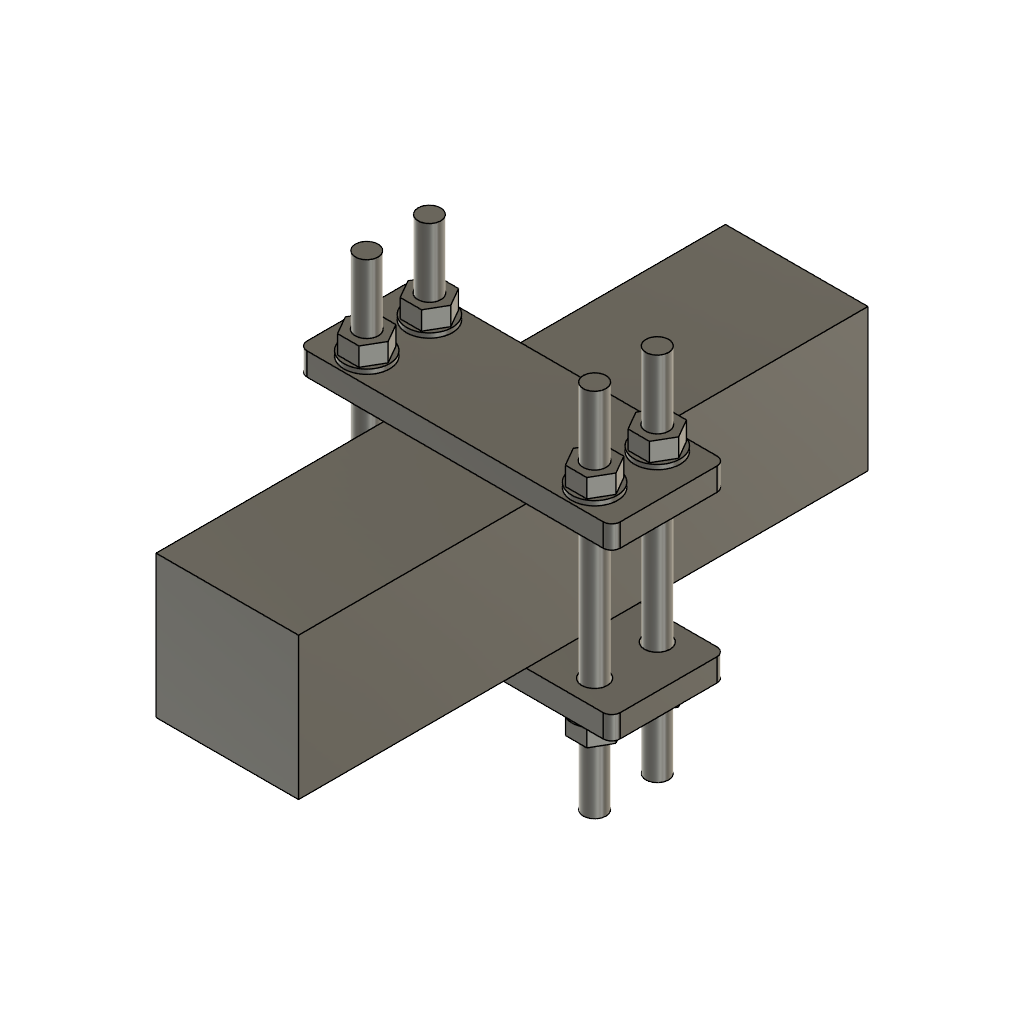
VISION_SWINE_Beam_Clamp_V1 (Autodesk Fusion 360 design; units mm, degrees)
part number: 2026-11-26-00-04-15-163
part number: 2026-11-26-00-04-15-727
part number: 2026-11-26-00-04-15-969
part number: 2026-11-26-00-04-18-167
part number: 2026-11-26-00-04-22-243
part number: 2026-11-26-00-04-23-402
part number: 2026-11-26-00-04-25-532
part number: 2026-11-26-00-04-30-687
part number: 2026-11-26-00-04-34-257
part number: 2026-11-26-00-04-42-118
part number: 2026-11-26-00-04-44-728
part number: 2026-11-26-00-04-49-048
part number: 2026-11-26-00-04-58-557
part number: 2026-11-26-00-05-03-923
part number: 2026-11-26-00-05-15-362
part number: 2026-11-26-00-05-19-142
part number: 2026-11-26-00-05-25-703
part number: 2026-11-26-00-05-39-825
part number: 2026-11-26-00-05-47-520
part number: 2026-11-26-00-06-03-111
part number: 2026-11-26-00-06-08-326
part number: 2026-11-26-00-06-16-988
part number: 2026-11-26-00-06-35-002
part number: 2026-11-26-00-06-44-910
Autodesk Fusion 360 part; units mm, degrees
ref_plane "WorkPlane1" through (-25, 0, 0) normal (1, 0, 0) x (0, 1, 0) in component "Beam_reference"
ref_plane "WorkPlane2" through (0, -100, 0) normal (0, 1, 0) x (0, 0, 1) in component "Beam_reference"
ref_plane "WorkPlane3" through (25, 0, 0) normal (1, 0, 0) x (0, 1, 0) in component "Beam_reference"
ref_plane "WorkPlane4" through (0, 100, 0) normal (0, 1, 0) x (0, 0, 1) in component "Beam_reference"
sketch "Sketch1" plane through (0, 0, 0) normal (0, 0, 1) x (1, 0, 0) in component "Beam_reference"
  line L0 (-25, -100) -> (24.9879, -99.9365)
  line L1 (24.9879, -99.9365) -> (25, 100)
  line L2 (25, 100) -> (-24.9879, 99.9365)
  line L3 (-24.9879, 99.9365) -> (-25, -100)
extrude "Rectangular blank" add sketch "Sketch1" along normal blind 50 makes body 1 in component "Beam_reference"
ref_plane "WorkPlane1" through (0, 0, -8) normal (0, 0, 1) x (1, 0, 0) in component "Lower_plate"
ref_plane "WorkPlane2" through (-55, 0, 0) normal (1, 0, 0) x (0, 1, 0) in component "Lower_plate"
ref_plane "WorkPlane3" through (0, -20, 0) normal (0, 1, 0) x (0, 0, 1) in component "Lower_plate"
ref_plane "WorkPlane4" through (55, 0, 0) normal (1, 0, 0) x (0, 1, 0) in component "Lower_plate"
ref_plane "WorkPlane5" through (0, 20, 0) normal (0, 1, 0) x (0, 0, 1) in component "Lower_plate"
sketch "Sketch1 (2)" plane through (0, 0, -8) normal (0, 0, 1) x (1, 0, 0) in component "Lower_plate"
  line L0 (-55, -20) -> (55, -20)
  line L1 (55, -20) -> (55, 20)
  line L2 (55, 20) -> (-55, 20)
  line L3 (-55, 20) -> (-55, -20)
extrude "Rectangular blank'" add sketch "Sketch1 (2)" along normal blind 8 separate body makes body 2 in component "Lower_plate"
fillet "Plate corners R" radius 3 4 edges at (-55, 20, -4) (55, 20, -4) (55, -20, -4) (-55, -20, -4) on bodies 2 in component "Lower_plate"
ref_plane "WorkPlane6" through (-40, 0, 0) normal (1, 0, 0) x (0, 1, 0) in component "Lower_plate"
ref_plane "WorkPlane7" through (0, -11, 0) normal (0, 1, 0) x (0, 0, 1) in component "Lower_plate"
sketch "Sketch2" plane through (0, 0, -8) normal (0, 0, 1) x (1, 0, 0) in component "Lower_plate"
  circle A0 centre (-40, -11) radius 4.5
  dimension "d51" = 9
  measures "d51" diameter of A0
extrude "M8 clearance 1" cut sketch "Sketch2" along normal blind 8 bodies 2 in component "Lower_plate"
ref_plane "WorkPlane8" through (0, 11, 0) normal (0, 1, 0) x (0, 0, 1) in component "Lower_plate"
sketch "Sketch3" plane through (0, 0, -8) normal (0, 0, 1) x (1, 0, 0) in component "Lower_plate"
  circle A0 centre (-40, 11) radius 4.5
  dimension "d56" = 9
  measures "d56" diameter of A0
extrude "M8 clearance 2" cut sketch "Sketch3" along normal blind 8 bodies 2 in component "Lower_plate"
ref_plane "WorkPlane9" through (40, 0, 0) normal (1, 0, 0) x (0, 1, 0) in component "Lower_plate"
sketch "Sketch4" plane through (0, 0, -8) normal (0, 0, 1) x (1, 0, 0) in component "Lower_plate"
  circle A0 centre (40, -11) radius 4.5
  dimension "d61" = 9
  measures "d61" diameter of A0
extrude "M8 clearance 3" cut sketch "Sketch4" along normal blind 8 bodies 2 in component "Lower_plate"
sketch "Sketch5" plane through (0, 0, -8) normal (0, 0, 1) x (1, 0, 0) in component "Lower_plate"
  circle A0 centre (40, 11) radius 4.5
  dimension "d64" = 9
  measures "d64" diameter of A0
extrude "M8 clearance 4" cut sketch "Sketch5" along normal blind 8 bodies 2 in component "Lower_plate"
ref_plane "WorkPlane1" through (0, 0, 50) normal (0, 0, 1) x (1, 0, 0) in component "Upper_plate"
ref_plane "WorkPlane2" through (-55, 0, 0) normal (1, 0, 0) x (0, 1, 0) in component "Upper_plate"
ref_plane "WorkPlane3" through (0, -20, 0) normal (0, 1, 0) x (0, 0, 1) in component "Upper_plate"
ref_plane "WorkPlane4" through (55, 0, 0) normal (1, 0, 0) x (0, 1, 0) in component "Upper_plate"
ref_plane "WorkPlane5" through (0, 20, 0) normal (0, 1, 0) x (0, 0, 1) in component "Upper_plate"
sketch "Sketch1 (3)" plane through (0, 0, 50) normal (0, 0, 1) x (1, 0, 0) in component "Upper_plate"
  line L0 (-55, -20) -> (55, -20)
  line L1 (55, -20) -> (55, 20)
  line L2 (55, 20) -> (-55, 20)
  line L3 (-55, 20) -> (-55, -20)
extrude "Rectangular blank''" add sketch "Sketch1 (3)" along normal blind 8 separate body makes body 3 in component "Upper_plate"
fillet "Plate corners R'" radius 3 4 edges at (-55, 20, 54) (55, 20, 54) (55, -20, 54) (-55, -20, 54) on bodies 3 in component "Upper_plate"
ref_plane "WorkPlane6" through (-40, 0, 0) normal (1, 0, 0) x (0, 1, 0) in component "Upper_plate"
ref_plane "WorkPlane7" through (0, -11, 0) normal (0, 1, 0) x (0, 0, 1) in component "Upper_plate"
sketch "Sketch2 (2)" plane through (0, 0, 50) normal (0, 0, 1) x (1, 0, 0) in component "Upper_plate"
  circle A0 centre (-40, -11) radius 4.5
  dimension "d85" = 9
  measures "d85" diameter of A0
extrude "M8 clearance 1'" cut sketch "Sketch2 (2)" along normal blind 8 bodies 3 in component "Upper_plate"
ref_plane "WorkPlane8" through (0, 11, 0) normal (0, 1, 0) x (0, 0, 1) in component "Upper_plate"
sketch "Sketch3 (2)" plane through (0, 0, 50) normal (0, 0, 1) x (1, 0, 0) in component "Upper_plate"
  circle A0 centre (-40, 11) radius 4.5
  dimension "d90" = 9
  measures "d90" diameter of A0
extrude "M8 clearance 2'" cut sketch "Sketch3 (2)" along normal blind 8 bodies 3 in component "Upper_plate"
ref_plane "WorkPlane9" through (40, 0, 0) normal (1, 0, 0) x (0, 1, 0) in component "Upper_plate"
sketch "Sketch4 (2)" plane through (0, 0, 50) normal (0, 0, 1) x (1, 0, 0) in component "Upper_plate"
  circle A0 centre (40, -11) radius 4.5
  dimension "d95" = 9
  measures "d95" diameter of A0
extrude "M8 clearance 3'" cut sketch "Sketch4 (2)" along normal blind 8 bodies 3 in component "Upper_plate"
sketch "Sketch5 (2)" plane through (0, 0, 50) normal (0, 0, 1) x (1, 0, 0) in component "Upper_plate"
  circle A0 centre (40, 11) radius 4.5
  dimension "d98" = 9
  measures "d98" diameter of A0
extrude "M8 clearance 4'" cut sketch "Sketch5 (2)" along normal blind 8 bodies 3 in component "Upper_plate"
ref_plane "WorkPlane1" through (0, 0, -40) normal (0, 0, 1) x (1, 0, 0) in component "Rod_1_ref"
ref_plane "WorkPlane2" through (-40, 0, 0) normal (1, 0, 0) x (0, 1, 0) in component "Rod_1_ref"
ref_plane "WorkPlane3" through (0, -11, 0) normal (0, 1, 0) x (0, 0, 1) in component "Rod_1_ref"
sketch "Sketch1 (4)" plane through (0, 0, -40) normal (0, 0, 1) x (1, 0, 0) in component "Rod_1_ref"
  circle A0 centre (-40, -11) radius 4
  dimension "d107" = 8
  measures "d107" diameter of A0
extrude "Smooth M8 rod envelope" add sketch "Sketch1 (4)" along normal blind 130 separate body makes body 4 in component "Rod_1_ref"
ref_plane "WorkPlane1" through (0, 0, -9.6) normal (0, 0, 1) x (1, 0, 0) in component "Washer_lower_1_ref"
ref_plane "WorkPlane2" through (-40, 0, 0) normal (1, 0, 0) x (0, 1, 0) in component "Washer_lower_1_ref"
ref_plane "WorkPlane3" through (0, -11, 0) normal (0, 1, 0) x (0, 0, 1) in component "Washer_lower_1_ref"
sketch "Sketch1 (5)" plane through (0, 0, -9.6) normal (0, 0, 1) x (1, 0, 0) in component "Washer_lower_1_ref"
  circle A0 centre (-40, -11) radius 8
  dimension "d116" = 16
  measures "d116" diameter of A0
extrude "Washer blank" add sketch "Sketch1 (5)" along normal blind 1.6 separate body makes body 5 in component "Washer_lower_1_ref"
sketch "Sketch2 (3)" plane through (0, 0, -9.6) normal (0, 0, 1) x (1, 0, 0) in component "Washer_lower_1_ref"
  circle A0 centre (-40, -11) radius 4.2
  dimension "d119" = 8.4
  measures "d119" diameter of A0
extrude "Washer bore" cut sketch "Sketch2 (3)" along normal blind 1.6 bodies 5 in component "Washer_lower_1_ref"
ref_plane "WorkPlane1" through (0, 0, -16.1) normal (0, 0, 1) x (1, 0, 0) in component "Nut_lower_1_ref"
ref_plane "WorkPlane2" through (-32.4944, 0, 0) normal (1, 0, 0) x (0, 1, 0) in component "Nut_lower_1_ref"
ref_plane "WorkPlane3" through (0, -11, 0) normal (0, 1, 0) x (0, 0, 1) in component "Nut_lower_1_ref"
ref_plane "WorkPlane4" through (-36.2472, 0, 0) normal (1, 0, 0) x (0, 1, 0) in component "Nut_lower_1_ref"
ref_plane "WorkPlane5" through (0, -4.5, 0) normal (0, 1, 0) x (0, 0, 1) in component "Nut_lower_1_ref"
ref_plane "WorkPlane6" through (-43.7528, 0, 0) normal (1, 0, 0) x (0, 1, 0) in component "Nut_lower_1_ref"
ref_plane "WorkPlane7" through (-47.5056, 0, 0) normal (1, 0, 0) x (0, 1, 0) in component "Nut_lower_1_ref"
ref_plane "WorkPlane8" through (0, -17.5, 0) normal (0, 1, 0) x (0, 0, 1) in component "Nut_lower_1_ref"
sketch "Sketch1 (6)" plane through (0, 0, -16.1) normal (0, 0, 1) x (1, 0, 0) in component "Nut_lower_1_ref"
  line L0 (-32.4944, -11) -> (-36.2472, -4.5)
  line L1 (-36.2472, -4.5) -> (-43.7528, -4.5)
  line L2 (-43.7528, -4.5) -> (-47.5056, -11)
  line L3 (-47.5056, -11) -> (-43.7528, -17.5)
  line L4 (-43.7528, -17.5) -> (-36.2472, -17.5)
  line L5 (-36.2472, -17.5) -> (-32.4944, -11)
extrude "Hex nut reference" add sketch "Sketch1 (6)" along normal blind 6.5 separate body makes body 6 in component "Nut_lower_1_ref"
ref_plane "WorkPlane9" through (-40, 0, 0) normal (1, 0, 0) x (0, 1, 0) in component "Nut_lower_1_ref"
ref_plane "WorkPlane10" through (0, -11, 0) normal (0, 1, 0) x (0, 0, 1) in component "Nut_lower_1_ref"
sketch "Sketch2 (4)" plane through (0, 0, -16.1) normal (0, 0, 1) x (1, 0, 0) in component "Nut_lower_1_ref"
  circle A0 centre (-40, -11) radius 4.05
  dimension "d144" = 8.1
  measures "d144" diameter of A0
extrude "Thread envelope bore" cut sketch "Sketch2 (4)" along normal blind 6.5 bodies 6 in component "Nut_lower_1_ref"
ref_plane "WorkPlane1" through (0, 0, 58) normal (0, 0, 1) x (1, 0, 0) in component "Washer_upper_1_ref"
ref_plane "WorkPlane2" through (-40, 0, 0) normal (1, 0, 0) x (0, 1, 0) in component "Washer_upper_1_ref"
ref_plane "WorkPlane3" through (0, -11, 0) normal (0, 1, 0) x (0, 0, 1) in component "Washer_upper_1_ref"
sketch "Sketch1 (7)" plane through (0, 0, 58) normal (0, 0, 1) x (1, 0, 0) in component "Washer_upper_1_ref"
  circle A0 centre (-40, -11) radius 8
  dimension "d153" = 16
  measures "d153" diameter of A0
extrude "Washer blank'" add sketch "Sketch1 (7)" along normal blind 1.6 separate body makes body 7 in component "Washer_upper_1_ref"
sketch "Sketch2 (5)" plane through (0, 0, 58) normal (0, 0, 1) x (1, 0, 0) in component "Washer_upper_1_ref"
  circle A0 centre (-40, -11) radius 4.2
  dimension "d156" = 8.4
  measures "d156" diameter of A0
extrude "Washer bore'" cut sketch "Sketch2 (5)" along normal blind 1.6 bodies 7 in component "Washer_upper_1_ref"
ref_plane "WorkPlane1" through (0, 0, 59.6) normal (0, 0, 1) x (1, 0, 0) in component "Nut_upper_1_ref"
ref_plane "WorkPlane2" through (-32.4944, 0, 0) normal (1, 0, 0) x (0, 1, 0) in component "Nut_upper_1_ref"
ref_plane "WorkPlane3" through (0, -11, 0) normal (0, 1, 0) x (0, 0, 1) in component "Nut_upper_1_ref"
ref_plane "WorkPlane4" through (-36.2472, 0, 0) normal (1, 0, 0) x (0, 1, 0) in component "Nut_upper_1_ref"
ref_plane "WorkPlane5" through (0, -4.5, 0) normal (0, 1, 0) x (0, 0, 1) in component "Nut_upper_1_ref"
ref_plane "WorkPlane6" through (-43.7528, 0, 0) normal (1, 0, 0) x (0, 1, 0) in component "Nut_upper_1_ref"
ref_plane "WorkPlane7" through (-47.5056, 0, 0) normal (1, 0, 0) x (0, 1, 0) in component "Nut_upper_1_ref"
ref_plane "WorkPlane8" through (0, -17.5, 0) normal (0, 1, 0) x (0, 0, 1) in component "Nut_upper_1_ref"
sketch "Sketch1 (8)" plane through (0, 0, 59.6) normal (0, 0, 1) x (1, 0, 0) in component "Nut_upper_1_ref"
  line L0 (-32.4944, -11) -> (-36.2472, -4.5)
  line L1 (-36.2472, -4.5) -> (-43.7528, -4.5)
  line L2 (-43.7528, -4.5) -> (-47.5056, -11)
  line L3 (-47.5056, -11) -> (-43.7528, -17.5)
  line L4 (-43.7528, -17.5) -> (-36.2472, -17.5)
  line L5 (-36.2472, -17.5) -> (-32.4944, -11)
extrude "Hex nut reference'" add sketch "Sketch1 (8)" along normal blind 6.5 separate body makes body 8 in component "Nut_upper_1_ref"
ref_plane "WorkPlane9" through (-40, 0, 0) normal (1, 0, 0) x (0, 1, 0) in component "Nut_upper_1_ref"
ref_plane "WorkPlane10" through (0, -11, 0) normal (0, 1, 0) x (0, 0, 1) in component "Nut_upper_1_ref"
sketch "Sketch2 (6)" plane through (0, 0, 59.6) normal (0, 0, 1) x (1, 0, 0) in component "Nut_upper_1_ref"
  circle A0 centre (-40, -11) radius 4.05
  dimension "d181" = 8.1
  measures "d181" diameter of A0
extrude "Thread envelope bore'" cut sketch "Sketch2 (6)" along normal blind 6.5 bodies 8 in component "Nut_upper_1_ref"
ref_plane "WorkPlane1" through (0, 0, -40) normal (0, 0, 1) x (1, 0, 0) in component "Rod_2_ref"
ref_plane "WorkPlane2" through (-40, 0, 0) normal (1, 0, 0) x (0, 1, 0) in component "Rod_2_ref"
ref_plane "WorkPlane3" through (0, 11, 0) normal (0, 1, 0) x (0, 0, 1) in component "Rod_2_ref"
sketch "Sketch1 (9)" plane through (0, 0, -40) normal (0, 0, 1) x (1, 0, 0) in component "Rod_2_ref"
  circle A0 centre (-40, 11) radius 4
  dimension "d190" = 8
  measures "d190" diameter of A0
extrude "Smooth M8 rod envelope'" add sketch "Sketch1 (9)" along normal blind 130 separate body makes body 9 in component "Rod_2_ref"
ref_plane "WorkPlane1" through (0, 0, -9.6) normal (0, 0, 1) x (1, 0, 0) in component "Washer_lower_2_ref"
ref_plane "WorkPlane2" through (-40, 0, 0) normal (1, 0, 0) x (0, 1, 0) in component "Washer_lower_2_ref"
ref_plane "WorkPlane3" through (0, 11, 0) normal (0, 1, 0) x (0, 0, 1) in component "Washer_lower_2_ref"
sketch "Sketch1 (10)" plane through (0, 0, -9.6) normal (0, 0, 1) x (1, 0, 0) in component "Washer_lower_2_ref"
  circle A0 centre (-40, 11) radius 8
  dimension "d199" = 16
  measures "d199" diameter of A0
extrude "Washer blank''" add sketch "Sketch1 (10)" along normal blind 1.6 separate body makes body 10 in component "Washer_lower_2_ref"
sketch "Sketch2 (7)" plane through (0, 0, -9.6) normal (0, 0, 1) x (1, 0, 0) in component "Washer_lower_2_ref"
  circle A0 centre (-40, 11) radius 4.2
  dimension "d202" = 8.4
  measures "d202" diameter of A0
extrude "Washer bore''" cut sketch "Sketch2 (7)" along normal blind 1.6 bodies 10 in component "Washer_lower_2_ref"
ref_plane "WorkPlane1" through (0, 0, -16.1) normal (0, 0, 1) x (1, 0, 0) in component "Nut_lower_2_ref"
ref_plane "WorkPlane2" through (-32.4944, 0, 0) normal (1, 0, 0) x (0, 1, 0) in component "Nut_lower_2_ref"
ref_plane "WorkPlane3" through (0, 11, 0) normal (0, 1, 0) x (0, 0, 1) in component "Nut_lower_2_ref"
ref_plane "WorkPlane4" through (-36.2472, 0, 0) normal (1, 0, 0) x (0, 1, 0) in component "Nut_lower_2_ref"
ref_plane "WorkPlane5" through (0, 17.5, 0) normal (0, 1, 0) x (0, 0, 1) in component "Nut_lower_2_ref"
ref_plane "WorkPlane6" through (-43.7528, 0, 0) normal (1, 0, 0) x (0, 1, 0) in component "Nut_lower_2_ref"
ref_plane "WorkPlane7" through (-47.5056, 0, 0) normal (1, 0, 0) x (0, 1, 0) in component "Nut_lower_2_ref"
ref_plane "WorkPlane8" through (0, 4.5, 0) normal (0, 1, 0) x (0, 0, 1) in component "Nut_lower_2_ref"
sketch "Sketch1 (11)" plane through (0, 0, -16.1) normal (0, 0, 1) x (1, 0, 0) in component "Nut_lower_2_ref"
  line L0 (-32.4944, 11) -> (-36.2472, 17.5)
  line L1 (-36.2472, 17.5) -> (-43.7528, 17.5)
  line L2 (-43.7528, 17.5) -> (-47.5056, 11)
  line L3 (-47.5056, 11) -> (-43.7528, 4.5)
  line L4 (-43.7528, 4.5) -> (-36.2472, 4.5)
  line L5 (-36.2472, 4.5) -> (-32.4944, 11)
extrude "Hex nut reference''" add sketch "Sketch1 (11)" along normal blind 6.5 separate body makes body 11 in component "Nut_lower_2_ref"
ref_plane "WorkPlane9" through (-40, 0, 0) normal (1, 0, 0) x (0, 1, 0) in component "Nut_lower_2_ref"
ref_plane "WorkPlane10" through (0, 11, 0) normal (0, 1, 0) x (0, 0, 1) in component "Nut_lower_2_ref"
sketch "Sketch2 (8)" plane through (0, 0, -16.1) normal (0, 0, 1) x (1, 0, 0) in component "Nut_lower_2_ref"
  circle A0 centre (-40, 11) radius 4.05
  dimension "d227" = 8.1
  measures "d227" diameter of A0
extrude "Thread envelope bore''" cut sketch "Sketch2 (8)" along normal blind 6.5 bodies 11 in component "Nut_lower_2_ref"
ref_plane "WorkPlane1" through (0, 0, 58) normal (0, 0, 1) x (1, 0, 0) in component "Washer_upper_2_ref"
ref_plane "WorkPlane2" through (-40, 0, 0) normal (1, 0, 0) x (0, 1, 0) in component "Washer_upper_2_ref"
ref_plane "WorkPlane3" through (0, 11, 0) normal (0, 1, 0) x (0, 0, 1) in component "Washer_upper_2_ref"
sketch "Sketch1 (12)" plane through (0, 0, 58) normal (0, 0, 1) x (1, 0, 0) in component "Washer_upper_2_ref"
  circle A0 centre (-40, 11) radius 8
  dimension "d236" = 16
  measures "d236" diameter of A0
extrude "Washer blank'''" add sketch "Sketch1 (12)" along normal blind 1.6 separate body makes body 12 in component "Washer_upper_2_ref"
sketch "Sketch2 (9)" plane through (0, 0, 58) normal (0, 0, 1) x (1, 0, 0) in component "Washer_upper_2_ref"
  circle A0 centre (-40, 11) radius 4.2
  dimension "d239" = 8.4
  measures "d239" diameter of A0
extrude "Washer bore'''" cut sketch "Sketch2 (9)" along normal blind 1.6 bodies 12 in component "Washer_upper_2_ref"
ref_plane "WorkPlane1" through (0, 0, 59.6) normal (0, 0, 1) x (1, 0, 0) in component "Nut_upper_2_ref"
ref_plane "WorkPlane2" through (-32.4944, 0, 0) normal (1, 0, 0) x (0, 1, 0) in component "Nut_upper_2_ref"
ref_plane "WorkPlane3" through (0, 11, 0) normal (0, 1, 0) x (0, 0, 1) in component "Nut_upper_2_ref"
ref_plane "WorkPlane4" through (-36.2472, 0, 0) normal (1, 0, 0) x (0, 1, 0) in component "Nut_upper_2_ref"
ref_plane "WorkPlane5" through (0, 17.5, 0) normal (0, 1, 0) x (0, 0, 1) in component "Nut_upper_2_ref"
ref_plane "WorkPlane6" through (-43.7528, 0, 0) normal (1, 0, 0) x (0, 1, 0) in component "Nut_upper_2_ref"
ref_plane "WorkPlane7" through (-47.5056, 0, 0) normal (1, 0, 0) x (0, 1, 0) in component "Nut_upper_2_ref"
ref_plane "WorkPlane8" through (0, 4.5, 0) normal (0, 1, 0) x (0, 0, 1) in component "Nut_upper_2_ref"
sketch "Sketch1 (13)" plane through (0, 0, 59.6) normal (0, 0, 1) x (1, 0, 0) in component "Nut_upper_2_ref"
  line L0 (-32.4944, 11) -> (-36.2472, 17.5)
  line L1 (-36.2472, 17.5) -> (-43.7528, 17.5)
  line L2 (-43.7528, 17.5) -> (-47.5056, 11)
  line L3 (-47.5056, 11) -> (-43.7528, 4.5)
  line L4 (-43.7528, 4.5) -> (-36.2472, 4.5)
  line L5 (-36.2472, 4.5) -> (-32.4944, 11)
extrude "Hex nut reference'''" add sketch "Sketch1 (13)" along normal blind 6.5 separate body makes body 13 in component "Nut_upper_2_ref"
ref_plane "WorkPlane9" through (-40, 0, 0) normal (1, 0, 0) x (0, 1, 0) in component "Nut_upper_2_ref"
ref_plane "WorkPlane10" through (0, 11, 0) normal (0, 1, 0) x (0, 0, 1) in component "Nut_upper_2_ref"
sketch "Sketch2 (10)" plane through (0, 0, 59.6) normal (0, 0, 1) x (1, 0, 0) in component "Nut_upper_2_ref"
  circle A0 centre (-40, 11) radius 4.05
  dimension "d264" = 8.1
  measures "d264" diameter of A0
extrude "Thread envelope bore'''" cut sketch "Sketch2 (10)" along normal blind 6.5 bodies 13 in component "Nut_upper_2_ref"
ref_plane "WorkPlane1" through (0, 0, -40) normal (0, 0, 1) x (1, 0, 0) in component "Rod_3_ref"
ref_plane "WorkPlane2" through (40, 0, 0) normal (1, 0, 0) x (0, 1, 0) in component "Rod_3_ref"
ref_plane "WorkPlane3" through (0, -11, 0) normal (0, 1, 0) x (0, 0, 1) in component "Rod_3_ref"
sketch "Sketch1 (14)" plane through (0, 0, -40) normal (0, 0, 1) x (1, 0, 0) in component "Rod_3_ref"
  circle A0 centre (40, -11) radius 4
  dimension "d273" = 8
  measures "d273" diameter of A0
extrude "Smooth M8 rod envelope''" add sketch "Sketch1 (14)" along normal blind 130 separate body makes body 14 in component "Rod_3_ref"
ref_plane "WorkPlane1" through (0, 0, -9.6) normal (0, 0, 1) x (1, 0, 0) in component "Washer_lower_3_ref"
ref_plane "WorkPlane2" through (40, 0, 0) normal (1, 0, 0) x (0, 1, 0) in component "Washer_lower_3_ref"
ref_plane "WorkPlane3" through (0, -11, 0) normal (0, 1, 0) x (0, 0, 1) in component "Washer_lower_3_ref"
sketch "Sketch1 (15)" plane through (0, 0, -9.6) normal (0, 0, 1) x (1, 0, 0) in component "Washer_lower_3_ref"
  circle A0 centre (40, -11) radius 8
  dimension "d282" = 16
  measures "d282" diameter of A0
extrude "Washer blank''''" add sketch "Sketch1 (15)" along normal blind 1.6 separate body makes body 15 in component "Washer_lower_3_ref"
sketch "Sketch2 (11)" plane through (0, 0, -9.6) normal (0, 0, 1) x (1, 0, 0) in component "Washer_lower_3_ref"
  circle A0 centre (40, -11) radius 4.2
  dimension "d285" = 8.4
  measures "d285" diameter of A0
extrude "Washer bore''''" cut sketch "Sketch2 (11)" along normal blind 1.6 bodies 15 in component "Washer_lower_3_ref"
ref_plane "WorkPlane1" through (0, 0, -16.1) normal (0, 0, 1) x (1, 0, 0) in component "Nut_lower_3_ref"
ref_plane "WorkPlane2" through (47.5056, 0, 0) normal (1, 0, 0) x (0, 1, 0) in component "Nut_lower_3_ref"
ref_plane "WorkPlane3" through (0, -11, 0) normal (0, 1, 0) x (0, 0, 1) in component "Nut_lower_3_ref"
ref_plane "WorkPlane4" through (43.7528, 0, 0) normal (1, 0, 0) x (0, 1, 0) in component "Nut_lower_3_ref"
ref_plane "WorkPlane5" through (0, -4.5, 0) normal (0, 1, 0) x (0, 0, 1) in component "Nut_lower_3_ref"
ref_plane "WorkPlane6" through (36.2472, 0, 0) normal (1, 0, 0) x (0, 1, 0) in component "Nut_lower_3_ref"
ref_plane "WorkPlane7" through (32.4944, 0, 0) normal (1, 0, 0) x (0, 1, 0) in component "Nut_lower_3_ref"
ref_plane "WorkPlane8" through (0, -17.5, 0) normal (0, 1, 0) x (0, 0, 1) in component "Nut_lower_3_ref"
sketch "Sketch1 (16)" plane through (0, 0, -16.1) normal (0, 0, 1) x (1, 0, 0) in component "Nut_lower_3_ref"
  line L0 (47.5056, -11) -> (43.7528, -4.5)
  line L1 (43.7528, -4.5) -> (36.2472, -4.5)
  line L2 (36.2472, -4.5) -> (32.4944, -11)
  line L3 (32.4944, -11) -> (36.2472, -17.5)
  line L4 (36.2472, -17.5) -> (43.7528, -17.5)
  line L5 (43.7528, -17.5) -> (47.5056, -11)
extrude "Hex nut reference''''" add sketch "Sketch1 (16)" along normal blind 6.5 separate body makes body 16 in component "Nut_lower_3_ref"
ref_plane "WorkPlane9" through (40, 0, 0) normal (1, 0, 0) x (0, 1, 0) in component "Nut_lower_3_ref"
ref_plane "WorkPlane10" through (0, -11, 0) normal (0, 1, 0) x (0, 0, 1) in component "Nut_lower_3_ref"
sketch "Sketch2 (12)" plane through (0, 0, -16.1) normal (0, 0, 1) x (1, 0, 0) in component "Nut_lower_3_ref"
  circle A0 centre (40, -11) radius 4.05
  dimension "d310" = 8.1
  measures "d310" diameter of A0
extrude "Thread envelope bore''''" cut sketch "Sketch2 (12)" along normal blind 6.5 bodies 16 in component "Nut_lower_3_ref"
ref_plane "WorkPlane1" through (0, 0, 58) normal (0, 0, 1) x (1, 0, 0) in component "Washer_upper_3_ref"
ref_plane "WorkPlane2" through (40, 0, 0) normal (1, 0, 0) x (0, 1, 0) in component "Washer_upper_3_ref"
ref_plane "WorkPlane3" through (0, -11, 0) normal (0, 1, 0) x (0, 0, 1) in component "Washer_upper_3_ref"
sketch "Sketch1 (17)" plane through (0, 0, 58) normal (0, 0, 1) x (1, 0, 0) in component "Washer_upper_3_ref"
  circle A0 centre (40, -11) radius 8
  dimension "d319" = 16
  measures "d319" diameter of A0
extrude "Washer blank'''''" add sketch "Sketch1 (17)" along normal blind 1.6 separate body makes body 17 in component "Washer_upper_3_ref"
sketch "Sketch2 (13)" plane through (0, 0, 58) normal (0, 0, 1) x (1, 0, 0) in component "Washer_upper_3_ref"
  circle A0 centre (40, -11) radius 4.2
  dimension "d322" = 8.4
  measures "d322" diameter of A0
extrude "Washer bore'''''" cut sketch "Sketch2 (13)" along normal blind 1.6 bodies 17 in component "Washer_upper_3_ref"
ref_plane "WorkPlane1" through (0, 0, 59.6) normal (0, 0, 1) x (1, 0, 0) in component "Nut_upper_3_ref"
ref_plane "WorkPlane2" through (47.5056, 0, 0) normal (1, 0, 0) x (0, 1, 0) in component "Nut_upper_3_ref"
ref_plane "WorkPlane3" through (0, -11, 0) normal (0, 1, 0) x (0, 0, 1) in component "Nut_upper_3_ref"
ref_plane "WorkPlane4" through (43.7528, 0, 0) normal (1, 0, 0) x (0, 1, 0) in component "Nut_upper_3_ref"
ref_plane "WorkPlane5" through (0, -4.5, 0) normal (0, 1, 0) x (0, 0, 1) in component "Nut_upper_3_ref"
ref_plane "WorkPlane6" through (36.2472, 0, 0) normal (1, 0, 0) x (0, 1, 0) in component "Nut_upper_3_ref"
ref_plane "WorkPlane7" through (32.4944, 0, 0) normal (1, 0, 0) x (0, 1, 0) in component "Nut_upper_3_ref"
ref_plane "WorkPlane8" through (0, -17.5, 0) normal (0, 1, 0) x (0, 0, 1) in component "Nut_upper_3_ref"
sketch "Sketch1 (18)" plane through (0, 0, 59.6) normal (0, 0, 1) x (1, 0, 0) in component "Nut_upper_3_ref"
  line L0 (47.5056, -11) -> (43.7528, -4.5)
  line L1 (43.7528, -4.5) -> (36.2472, -4.5)
  line L2 (36.2472, -4.5) -> (32.4944, -11)
  line L3 (32.4944, -11) -> (36.2472, -17.5)
  line L4 (36.2472, -17.5) -> (43.7528, -17.5)
  line L5 (43.7528, -17.5) -> (47.5056, -11)
extrude "Hex nut reference'''''" add sketch "Sketch1 (18)" along normal blind 6.5 separate body makes body 18 in component "Nut_upper_3_ref"
ref_plane "WorkPlane9" through (40, 0, 0) normal (1, 0, 0) x (0, 1, 0) in component "Nut_upper_3_ref"
ref_plane "WorkPlane10" through (0, -11, 0) normal (0, 1, 0) x (0, 0, 1) in component "Nut_upper_3_ref"
sketch "Sketch2 (14)" plane through (0, 0, 59.6) normal (0, 0, 1) x (1, 0, 0) in component "Nut_upper_3_ref"
  circle A0 centre (40, -11) radius 4.05
  dimension "d347" = 8.1
  measures "d347" diameter of A0
extrude "Thread envelope bore'''''" cut sketch "Sketch2 (14)" along normal blind 6.5 bodies 18 in component "Nut_upper_3_ref"
ref_plane "WorkPlane1" through (0, 0, -40) normal (0, 0, 1) x (1, 0, 0) in component "Rod_4_ref"
ref_plane "WorkPlane2" through (40, 0, 0) normal (1, 0, 0) x (0, 1, 0) in component "Rod_4_ref"
ref_plane "WorkPlane3" through (0, 11, 0) normal (0, 1, 0) x (0, 0, 1) in component "Rod_4_ref"
sketch "Sketch1 (19)" plane through (0, 0, -40) normal (0, 0, 1) x (1, 0, 0) in component "Rod_4_ref"
  circle A0 centre (40, 11) radius 4
  dimension "d356" = 8
  measures "d356" diameter of A0
extrude "Smooth M8 rod envelope'''" add sketch "Sketch1 (19)" along normal blind 130 separate body makes body 19 in component "Rod_4_ref"
ref_plane "WorkPlane1" through (0, 0, -9.6) normal (0, 0, 1) x (1, 0, 0) in component "Washer_lower_4_ref"
ref_plane "WorkPlane2" through (40, 0, 0) normal (1, 0, 0) x (0, 1, 0) in component "Washer_lower_4_ref"
ref_plane "WorkPlane3" through (0, 11, 0) normal (0, 1, 0) x (0, 0, 1) in component "Washer_lower_4_ref"
sketch "Sketch1 (20)" plane through (0, 0, -9.6) normal (0, 0, 1) x (1, 0, 0) in component "Washer_lower_4_ref"
  circle A0 centre (40, 11) radius 8
  dimension "d365" = 16
  measures "d365" diameter of A0
extrude "Washer blank''''''" add sketch "Sketch1 (20)" along normal blind 1.6 separate body makes body 20 in component "Washer_lower_4_ref"
sketch "Sketch2 (15)" plane through (0, 0, -9.6) normal (0, 0, 1) x (1, 0, 0) in component "Washer_lower_4_ref"
  circle A0 centre (40, 11) radius 4.2
  dimension "d368" = 8.4
  measures "d368" diameter of A0
extrude "Washer bore''''''" cut sketch "Sketch2 (15)" along normal blind 1.6 bodies 20 in component "Washer_lower_4_ref"
ref_plane "WorkPlane1" through (0, 0, -16.1) normal (0, 0, 1) x (1, 0, 0) in component "Nut_lower_4_ref"
ref_plane "WorkPlane2" through (47.5056, 0, 0) normal (1, 0, 0) x (0, 1, 0) in component "Nut_lower_4_ref"
ref_plane "WorkPlane3" through (0, 11, 0) normal (0, 1, 0) x (0, 0, 1) in component "Nut_lower_4_ref"
ref_plane "WorkPlane4" through (43.7528, 0, 0) normal (1, 0, 0) x (0, 1, 0) in component "Nut_lower_4_ref"
ref_plane "WorkPlane5" through (0, 17.5, 0) normal (0, 1, 0) x (0, 0, 1) in component "Nut_lower_4_ref"
ref_plane "WorkPlane6" through (36.2472, 0, 0) normal (1, 0, 0) x (0, 1, 0) in component "Nut_lower_4_ref"
ref_plane "WorkPlane7" through (32.4944, 0, 0) normal (1, 0, 0) x (0, 1, 0) in component "Nut_lower_4_ref"
ref_plane "WorkPlane8" through (0, 4.5, 0) normal (0, 1, 0) x (0, 0, 1) in component "Nut_lower_4_ref"
sketch "Sketch1 (21)" plane through (0, 0, -16.1) normal (0, 0, 1) x (1, 0, 0) in component "Nut_lower_4_ref"
  line L0 (47.5056, 11) -> (43.7528, 17.5)
  line L1 (43.7528, 17.5) -> (36.2472, 17.5)
  line L2 (36.2472, 17.5) -> (32.4944, 11)
  line L3 (32.4944, 11) -> (36.2472, 4.5)
  line L4 (36.2472, 4.5) -> (43.7528, 4.5)
  line L5 (43.7528, 4.5) -> (47.5056, 11)
extrude "Hex nut reference''''''" add sketch "Sketch1 (21)" along normal blind 6.5 separate body makes body 21 in component "Nut_lower_4_ref"
ref_plane "WorkPlane9" through (40, 0, 0) normal (1, 0, 0) x (0, 1, 0) in component "Nut_lower_4_ref"
ref_plane "WorkPlane10" through (0, 11, 0) normal (0, 1, 0) x (0, 0, 1) in component "Nut_lower_4_ref"
sketch "Sketch2 (16)" plane through (0, 0, -16.1) normal (0, 0, 1) x (1, 0, 0) in component "Nut_lower_4_ref"
  circle A0 centre (40, 11) radius 4.05
  dimension "d393" = 8.1
  measures "d393" diameter of A0
extrude "Thread envelope bore''''''" cut sketch "Sketch2 (16)" along normal blind 6.5 bodies 21 in component "Nut_lower_4_ref"
ref_plane "WorkPlane1" through (0, 0, 58) normal (0, 0, 1) x (1, 0, 0) in component "Washer_upper_4_ref"
ref_plane "WorkPlane2" through (40, 0, 0) normal (1, 0, 0) x (0, 1, 0) in component "Washer_upper_4_ref"
ref_plane "WorkPlane3" through (0, 11, 0) normal (0, 1, 0) x (0, 0, 1) in component "Washer_upper_4_ref"
sketch "Sketch1 (22)" plane through (0, 0, 58) normal (0, 0, 1) x (1, 0, 0) in component "Washer_upper_4_ref"
  circle A0 centre (40, 11) radius 8
  dimension "d402" = 16
  measures "d402" diameter of A0
extrude "Washer blank'''''''" add sketch "Sketch1 (22)" along normal blind 1.6 separate body makes body 22 in component "Washer_upper_4_ref"
sketch "Sketch2 (17)" plane through (0, 0, 58) normal (0, 0, 1) x (1, 0, 0) in component "Washer_upper_4_ref"
  circle A0 centre (40, 11) radius 4.2
  dimension "d405" = 8.4
  measures "d405" diameter of A0
extrude "Washer bore'''''''" cut sketch "Sketch2 (17)" along normal blind 1.6 bodies 22 in component "Washer_upper_4_ref"
ref_plane "WorkPlane1" through (0, 0, 59.6) normal (0, 0, 1) x (1, 0, 0) in component "Nut_upper_4_ref"
ref_plane "WorkPlane2" through (47.5056, 0, 0) normal (1, 0, 0) x (0, 1, 0) in component "Nut_upper_4_ref"
ref_plane "WorkPlane3" through (0, 11, 0) normal (0, 1, 0) x (0, 0, 1) in component "Nut_upper_4_ref"
ref_plane "WorkPlane4" through (43.7528, 0, 0) normal (1, 0, 0) x (0, 1, 0) in component "Nut_upper_4_ref"
ref_plane "WorkPlane5" through (0, 17.5, 0) normal (0, 1, 0) x (0, 0, 1) in component "Nut_upper_4_ref"
ref_plane "WorkPlane6" through (36.2472, 0, 0) normal (1, 0, 0) x (0, 1, 0) in component "Nut_upper_4_ref"
ref_plane "WorkPlane7" through (32.4944, 0, 0) normal (1, 0, 0) x (0, 1, 0) in component "Nut_upper_4_ref"
ref_plane "WorkPlane8" through (0, 4.5, 0) normal (0, 1, 0) x (0, 0, 1) in component "Nut_upper_4_ref"
sketch "Sketch1 (23)" plane through (0, 0, 59.6) normal (0, 0, 1) x (1, 0, 0) in component "Nut_upper_4_ref"
  line L0 (47.5056, 11) -> (43.7528, 17.5)
  line L1 (43.7528, 17.5) -> (36.2472, 17.5)
  line L2 (36.2472, 17.5) -> (32.4944, 11)
  line L3 (32.4944, 11) -> (36.2472, 4.5)
  line L4 (36.2472, 4.5) -> (43.7528, 4.5)
  line L5 (43.7528, 4.5) -> (47.5056, 11)
extrude "Hex nut reference'''''''" add sketch "Sketch1 (23)" along normal blind 6.5 separate body makes body 23 in component "Nut_upper_4_ref"
ref_plane "WorkPlane9" through (40, 0, 0) normal (1, 0, 0) x (0, 1, 0) in component "Nut_upper_4_ref"
ref_plane "WorkPlane10" through (0, 11, 0) normal (0, 1, 0) x (0, 0, 1) in component "Nut_upper_4_ref"
sketch "Sketch2 (18)" plane through (0, 0, 59.6) normal (0, 0, 1) x (1, 0, 0) in component "Nut_upper_4_ref"
  circle A0 centre (40, 11) radius 4.05
  dimension "d430" = 8.1
  measures "d430" diameter of A0
extrude "Thread envelope bore'''''''" cut sketch "Sketch2 (18)" along normal blind 6.5 bodies 23 in component "Nut_upper_4_ref"
ref_plane "WorkPlane10" through (-12, 0, 0) normal (1, 0, 0) x (0, 1, 0) in component "Lower_plate"
ref_plane "WorkPlane11" through (0, -15, 0) normal (0, 1, 0) x (0, 0, 1) in component "Lower_plate"
ref_plane "WorkPlane12" through (12, 0, 0) normal (1, 0, 0) x (0, 1, 0) in component "Lower_plate"
ref_plane "WorkPlane13" through (0, 15, 0) normal (0, 1, 0) x (0, 0, 1) in component "Lower_plate"
sketch "Concept only - lower adapter footprint" plane through (0, 0, -8) normal (0, 0, 1) x (1, 0, 0) in component "Lower_plate"
  line L0 (-12, -15) -> (12, -15) construction
  line L1 (12, -15) -> (12, 15) construction
  line L2 (12, 15) -> (-12, 15) construction
  line L3 (-12, 15) -> (-12, -15) construction
component "Beam_reference" placed x (1, 0, 0) y (0, 1, 0) z (0, 0, 1) at (0, 0, 0)
component "Lower_plate" placed x (1, 0, 0) y (0, 1, 0) z (0, 0, 1) at (0, 0, 0)
component "Upper_plate" placed x (1, 0, 0) y (0, 1, 0) z (0, 0, 1) at (0, 0, 0)
component "Rod_1_ref" placed x (1, 0, 0) y (0, 1, 0) z (0, 0, 1) at (0, 0, 0)
component "Washer_lower_1_ref" placed x (1, 0, 0) y (0, 1, 0) z (0, 0, 1) at (0, 0, 0)
component "Nut_lower_1_ref" placed x (1, 0, 0) y (0, 1, 0) z (0, 0, 1) at (0, 0, 0)
component "Washer_upper_1_ref" placed x (1, 0, 0) y (0, 1, 0) z (0, 0, 1) at (0, 0, 0)
component "Nut_upper_1_ref" placed x (1, 0, 0) y (0, 1, 0) z (0, 0, 1) at (0, 0, 0)
component "Rod_2_ref" placed x (1, 0, 0) y (0, 1, 0) z (0, 0, 1) at (0, 0, 0)
component "Washer_lower_2_ref" placed x (1, 0, 0) y (0, 1, 0) z (0, 0, 1) at (0, 0, 0)
component "Nut_lower_2_ref" placed x (1, 0, 0) y (0, 1, 0) z (0, 0, 1) at (0, 0, 0)
component "Washer_upper_2_ref" placed x (1, 0, 0) y (0, 1, 0) z (0, 0, 1) at (0, 0, 0)
component "Nut_upper_2_ref" placed x (1, 0, 0) y (0, 1, 0) z (0, 0, 1) at (0, 0, 0)
component "Rod_3_ref" placed x (1, 0, 0) y (0, 1, 0) z (0, 0, 1) at (0, 0, 0)
component "Washer_lower_3_ref" placed x (1, 0, 0) y (0, 1, 0) z (0, 0, 1) at (0, 0, 0)
component "Nut_lower_3_ref" placed x (1, 0, 0) y (0, 1, 0) z (0, 0, 1) at (0, 0, 0)
component "Washer_upper_3_ref" placed x (1, 0, 0) y (0, 1, 0) z (0, 0, 1) at (0, 0, 0)
component "Nut_upper_3_ref" placed x (1, 0, 0) y (0, 1, 0) z (0, 0, 1) at (0, 0, 0)
component "Rod_4_ref" placed x (1, 0, 0) y (0, 1, 0) z (0, 0, 1) at (0, 0, 0)
component "Washer_lower_4_ref" placed x (1, 0, 0) y (0, 1, 0) z (0, 0, 1) at (0, 0, 0)
component "Nut_lower_4_ref" placed x (1, 0, 0) y (0, 1, 0) z (0, 0, 1) at (0, 0, 0)
component "Washer_upper_4_ref" placed x (1, 0, 0) y (0, 1, 0) z (0, 0, 1) at (0, 0, 0)
component "Nut_upper_4_ref" placed x (1, 0, 0) y (0, 1, 0) z (0, 0, 1) at (0, 0, 0)
equation "bcBeamW = 50 mm" comment "Beam Clamp V1 prototype"
equation "bcBeamH = 50 mm" comment "Beam Clamp V1 prototype"
equation "bcBeamL = 200 mm" comment "Beam Clamp V1 prototype"
equation "bcPlateW = 110 mm" comment "Beam Clamp V1 prototype"
equation "bcPlateD = 40 mm" comment "Beam Clamp V1 prototype"
equation "bcPlateT = 8 mm" comment "Beam Clamp V1 prototype"
equation "bcCornerR = 3 mm" comment "Beam Clamp V1 prototype"
equation "bcPitchX = 80 mm" comment "Beam Clamp V1 prototype"
equation "bcPitchY = 22 mm" comment "Beam Clamp V1 prototype"
equation "bcHoleD = 9 mm" comment "Beam Clamp V1 prototype"
equation "bcRodD = 8 mm" comment "Beam Clamp V1 prototype"
equation "bcRodL = 130 mm" comment "Beam Clamp V1 prototype"
equation "bcNutAF = 13 mm" comment "Beam Clamp V1 prototype"
equation "bcNutH = 6.5 mm" comment "Beam Clamp V1 prototype"
equation "bcNutBore = 8.1 mm" comment "Beam Clamp V1 prototype"
equation "bcWasherOD = 16 mm" comment "Beam Clamp V1 prototype"
equation "bcWasherID = 8.4 mm" comment "Beam Clamp V1 prototype"
equation "bcWasherT = 1.6 mm" comment "Beam Clamp V1 prototype"
equation "bcToolOD = 20 mm" comment "Beam Clamp V1 prototype"
equation "bcToolApproach = 30 mm" comment "Beam Clamp V1 prototype"
equation "bcEndAllowance = 2.5 mm" comment "Beam Clamp V1 prototype"
equation "bcSideAllowance = 1 mm" comment "Beam Clamp V1 prototype"
equation "d23 = -bcBeamW / 2"
equation "d25 = -bcBeamL / 2"
equation "d27 = bcBeamW / 2"
equation "d29 = bcBeamL / 2"
equation "d31 = bcBeamH"
equation "d33 = -bcPlateT"
equation "d35 = -bcPlateW / 2"
equation "d37 = -bcPlateD / 2"
equation "d39 = bcPlateW / 2"
equation "d41 = bcPlateD / 2"
equation "d43 = bcPlateT"
equation "d46 = bcCornerR"
equation "d47 = -bcPitchX / 2"
equation "d49 = -bcPitchY / 2"
equation "d51 = bcHoleD"
equation "d52 = bcPlateT"
equation "d54 = bcPitchY / 2"
equation "d56 = bcHoleD"
equation "d57 = bcPlateT"
equation "d59 = bcPitchX / 2"
equation "d61 = bcHoleD"
equation "d62 = bcPlateT"
equation "d64 = bcHoleD"
equation "d65 = bcPlateT"
equation "d67 = bcBeamH"
equation "d69 = -bcPlateW / 2"
equation "d71 = -bcPlateD / 2"
equation "d73 = bcPlateW / 2"
equation "d75 = bcPlateD / 2"
equation "d77 = bcPlateT"
equation "d80 = bcCornerR"
equation "d81 = -bcPitchX / 2"
equation "d83 = -bcPitchY / 2"
equation "d85 = bcHoleD"
equation "d86 = bcPlateT"
equation "d88 = bcPitchY / 2"
equation "d90 = bcHoleD"
equation "d91 = bcPlateT"
equation "d93 = bcPitchX / 2"
equation "d95 = bcHoleD"
equation "d96 = bcPlateT"
equation "d98 = bcHoleD"
equation "d99 = bcPlateT"
equation "d101 = ( bcBeamH - bcRodL ) / 2"
equation "d103 = -bcPitchX / 2"
equation "d105 = -bcPitchY / 2"
equation "d107 = bcRodD"
equation "d108 = bcRodL"
equation "d110 = -bcPlateT - bcWasherT"
equation "d112 = -bcPitchX / 2"
equation "d114 = -bcPitchY / 2"
equation "d116 = bcWasherOD"
equation "d117 = bcWasherT"
equation "d119 = bcWasherID"
equation "d120 = bcWasherT"
equation "d122 = -bcPlateT - bcWasherT - bcNutH"
equation "d124 = ( -bcPitchX / 2 ) + ( bcNutAF / 1.73205080756888 )"
equation "d126 = ( -bcPitchY / 2 ) + ( 0 mm )"
equation "d128 = ( -bcPitchX / 2 ) + ( bcNutAF / 1.73205080756888 / 2 )"
equation "d130 = ( -bcPitchY / 2 ) + ( bcNutAF / 2 )"
equation "d132 = ( -bcPitchX / 2 ) + ( -bcNutAF / 1.73205080756888 / 2 )"
equation "d134 = ( -bcPitchX / 2 ) + ( -bcNutAF / 1.73205080756888 )"
equation "d136 = ( -bcPitchY / 2 ) + ( -bcNutAF / 2 )"
equation "d138 = bcNutH"
equation "d140 = -bcPitchX / 2"
equation "d142 = -bcPitchY / 2"
equation "d144 = bcNutBore"
equation "d145 = bcNutH"
equation "d147 = bcBeamH + bcPlateT"
equation "d149 = -bcPitchX / 2"
equation "d151 = -bcPitchY / 2"
equation "d153 = bcWasherOD"
equation "d154 = bcWasherT"
equation "d156 = bcWasherID"
equation "d157 = bcWasherT"
equation "d159 = bcBeamH + bcPlateT + bcWasherT"
equation "d161 = ( -bcPitchX / 2 ) + ( bcNutAF / 1.73205080756888 )"
equation "d163 = ( -bcPitchY / 2 ) + ( 0 mm )"
equation "d165 = ( -bcPitchX / 2 ) + ( bcNutAF / 1.73205080756888 / 2 )"
equation "d167 = ( -bcPitchY / 2 ) + ( bcNutAF / 2 )"
equation "d169 = ( -bcPitchX / 2 ) + ( -bcNutAF / 1.73205080756888 / 2 )"
equation "d171 = ( -bcPitchX / 2 ) + ( -bcNutAF / 1.73205080756888 )"
equation "d173 = ( -bcPitchY / 2 ) + ( -bcNutAF / 2 )"
equation "d175 = bcNutH"
equation "d177 = -bcPitchX / 2"
equation "d179 = -bcPitchY / 2"
equation "d181 = bcNutBore"
equation "d182 = bcNutH"
equation "d184 = ( bcBeamH - bcRodL ) / 2"
equation "d186 = -bcPitchX / 2"
equation "d188 = bcPitchY / 2"
equation "d190 = bcRodD"
equation "d191 = bcRodL"
equation "d193 = -bcPlateT - bcWasherT"
equation "d195 = -bcPitchX / 2"
equation "d197 = bcPitchY / 2"
equation "d199 = bcWasherOD"
equation "d200 = bcWasherT"
equation "d202 = bcWasherID"
equation "d203 = bcWasherT"
equation "d205 = -bcPlateT - bcWasherT - bcNutH"
equation "d207 = ( -bcPitchX / 2 ) + ( bcNutAF / 1.73205080756888 )"
equation "d209 = ( bcPitchY / 2 ) + ( 0 mm )"
equation "d211 = ( -bcPitchX / 2 ) + ( bcNutAF / 1.73205080756888 / 2 )"
equation "d213 = ( bcPitchY / 2 ) + ( bcNutAF / 2 )"
equation "d215 = ( -bcPitchX / 2 ) + ( -bcNutAF / 1.73205080756888 / 2 )"
equation "d217 = ( -bcPitchX / 2 ) + ( -bcNutAF / 1.73205080756888 )"
equation "d219 = ( bcPitchY / 2 ) + ( -bcNutAF / 2 )"
equation "d221 = bcNutH"
equation "d223 = -bcPitchX / 2"
equation "d225 = bcPitchY / 2"
equation "d227 = bcNutBore"
equation "d228 = bcNutH"
equation "d230 = bcBeamH + bcPlateT"
equation "d232 = -bcPitchX / 2"
equation "d234 = bcPitchY / 2"
equation "d236 = bcWasherOD"
equation "d237 = bcWasherT"
equation "d239 = bcWasherID"
equation "d240 = bcWasherT"
equation "d242 = bcBeamH + bcPlateT + bcWasherT"
equation "d244 = ( -bcPitchX / 2 ) + ( bcNutAF / 1.73205080756888 )"
equation "d246 = ( bcPitchY / 2 ) + ( 0 mm )"
equation "d248 = ( -bcPitchX / 2 ) + ( bcNutAF / 1.73205080756888 / 2 )"
equation "d250 = ( bcPitchY / 2 ) + ( bcNutAF / 2 )"
equation "d252 = ( -bcPitchX / 2 ) + ( -bcNutAF / 1.73205080756888 / 2 )"
equation "d254 = ( -bcPitchX / 2 ) + ( -bcNutAF / 1.73205080756888 )"
equation "d256 = ( bcPitchY / 2 ) + ( -bcNutAF / 2 )"
equation "d258 = bcNutH"
equation "d260 = -bcPitchX / 2"
equation "d262 = bcPitchY / 2"
equation "d264 = bcNutBore"
equation "d265 = bcNutH"
equation "d267 = ( bcBeamH - bcRodL ) / 2"
equation "d269 = bcPitchX / 2"
equation "d271 = -bcPitchY / 2"
equation "d273 = bcRodD"
equation "d274 = bcRodL"
equation "d276 = -bcPlateT - bcWasherT"
equation "d278 = bcPitchX / 2"
equation "d280 = -bcPitchY / 2"
equation "d282 = bcWasherOD"
equation "d283 = bcWasherT"
equation "d285 = bcWasherID"
equation "d286 = bcWasherT"
equation "d288 = -bcPlateT - bcWasherT - bcNutH"
equation "d290 = ( bcPitchX / 2 ) + ( bcNutAF / 1.73205080756888 )"
equation "d292 = ( -bcPitchY / 2 ) + ( 0 mm )"
equation "d294 = ( bcPitchX / 2 ) + ( bcNutAF / 1.73205080756888 / 2 )"
equation "d296 = ( -bcPitchY / 2 ) + ( bcNutAF / 2 )"
equation "d298 = ( bcPitchX / 2 ) + ( -bcNutAF / 1.73205080756888 / 2 )"
equation "d300 = ( bcPitchX / 2 ) + ( -bcNutAF / 1.73205080756888 )"
equation "d302 = ( -bcPitchY / 2 ) + ( -bcNutAF / 2 )"
equation "d304 = bcNutH"
equation "d306 = bcPitchX / 2"
equation "d308 = -bcPitchY / 2"
equation "d310 = bcNutBore"
equation "d311 = bcNutH"
equation "d313 = bcBeamH + bcPlateT"
equation "d315 = bcPitchX / 2"
equation "d317 = -bcPitchY / 2"
equation "d319 = bcWasherOD"
equation "d320 = bcWasherT"
equation "d322 = bcWasherID"
equation "d323 = bcWasherT"
equation "d325 = bcBeamH + bcPlateT + bcWasherT"
equation "d327 = ( bcPitchX / 2 ) + ( bcNutAF / 1.73205080756888 )"
equation "d329 = ( -bcPitchY / 2 ) + ( 0 mm )"
equation "d331 = ( bcPitchX / 2 ) + ( bcNutAF / 1.73205080756888 / 2 )"
equation "d333 = ( -bcPitchY / 2 ) + ( bcNutAF / 2 )"
equation "d335 = ( bcPitchX / 2 ) + ( -bcNutAF / 1.73205080756888 / 2 )"
equation "d337 = ( bcPitchX / 2 ) + ( -bcNutAF / 1.73205080756888 )"
equation "d339 = ( -bcPitchY / 2 ) + ( -bcNutAF / 2 )"
equation "d341 = bcNutH"
equation "d343 = bcPitchX / 2"
equation "d345 = -bcPitchY / 2"
equation "d347 = bcNutBore"
equation "d348 = bcNutH"
equation "d350 = ( bcBeamH - bcRodL ) / 2"
equation "d352 = bcPitchX / 2"
equation "d354 = bcPitchY / 2"
equation "d356 = bcRodD"
equation "d357 = bcRodL"
equation "d359 = -bcPlateT - bcWasherT"
equation "d361 = bcPitchX / 2"
equation "d363 = bcPitchY / 2"
equation "d365 = bcWasherOD"
equation "d366 = bcWasherT"
equation "d368 = bcWasherID"
equation "d369 = bcWasherT"
equation "d371 = -bcPlateT - bcWasherT - bcNutH"
equation "d373 = ( bcPitchX / 2 ) + ( bcNutAF / 1.73205080756888 )"
equation "d375 = ( bcPitchY / 2 ) + ( 0 mm )"
equation "d377 = ( bcPitchX / 2 ) + ( bcNutAF / 1.73205080756888 / 2 )"
equation "d379 = ( bcPitchY / 2 ) + ( bcNutAF / 2 )"
equation "d381 = ( bcPitchX / 2 ) + ( -bcNutAF / 1.73205080756888 / 2 )"
equation "d383 = ( bcPitchX / 2 ) + ( -bcNutAF / 1.73205080756888 )"
equation "d385 = ( bcPitchY / 2 ) + ( -bcNutAF / 2 )"
equation "d387 = bcNutH"
equation "d389 = bcPitchX / 2"
equation "d391 = bcPitchY / 2"
equation "d393 = bcNutBore"
equation "d394 = bcNutH"
equation "d396 = bcBeamH + bcPlateT"
equation "d398 = bcPitchX / 2"
equation "d400 = bcPitchY / 2"
equation "d402 = bcWasherOD"
equation "d403 = bcWasherT"
equation "d405 = bcWasherID"
equation "d406 = bcWasherT"
equation "d408 = bcBeamH + bcPlateT + bcWasherT"
equation "d410 = ( bcPitchX / 2 ) + ( bcNutAF / 1.73205080756888 )"
equation "d412 = ( bcPitchY / 2 ) + ( 0 mm )"
equation "d414 = ( bcPitchX / 2 ) + ( bcNutAF / 1.73205080756888 / 2 )"
equation "d416 = ( bcPitchY / 2 ) + ( bcNutAF / 2 )"
equation "d418 = ( bcPitchX / 2 ) + ( -bcNutAF / 1.73205080756888 / 2 )"
equation "d420 = ( bcPitchX / 2 ) + ( -bcNutAF / 1.73205080756888 )"
equation "d422 = ( bcPitchY / 2 ) + ( -bcNutAF / 2 )"
equation "d424 = bcNutH"
equation "d426 = bcPitchX / 2"
equation "d428 = bcPitchY / 2"
equation "d430 = bcNutBore"
equation "d431 = bcNutH"
equation "bcInterfaceW = 24 mm" comment "Provisional adapter footprint"
equation "bcInterfaceD = 30 mm" comment "Provisional adapter footprint"
equation "d435 = -bcInterfaceW / 2"
equation "d437 = -bcInterfaceD / 2"
equation "d439 = bcInterfaceW / 2"
equation "d441 = bcInterfaceD / 2"
